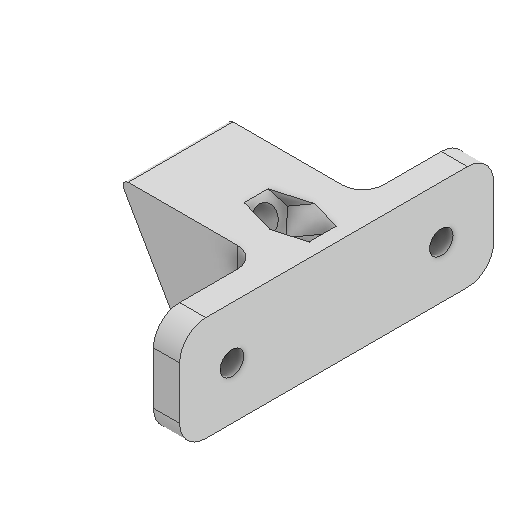
# Autodesk Inventor part: 3DP_PLA_Alu_Frame_Brace_REVB
Saved by Autodesk Inventor 2027 (Build 310192060, 192F)
## iProperties
Created: 2026-03-01
Part Number: 3DP_PLA_Alu_Frame_Brace_REVB
Material: Generic
Document SubType Name: Modeling
Designer: User
Density: 1 g/cm^3
Appearance: Default
Author: User
Autodesk Inventor part; units mm, degrees
ref_plane "YZ Plane" through (0, 0, 0) normal (1, 0, 0) x (0, 1, 0)
sketch "Sketch1" plane through (0, 0, 0) normal (0, 0, 1) x (1, 0, 0)
  line L0 (-5, 10) -> (0, 10)
  line L1 (0, 10) -> (0, -10)
  line L2 (0, -10) -> (-5, -10)
  line L3 (-5, -10) -> (-5, 10)
  point P0 (0, 0)
  point P1 (0, 0)
  dimension "d0" = 20
  dimension "d1" = 10
  dimension "d2" = 5
  constraints: 8 end point, 2 parallel, 1 horizontal, 1 midpoint, 1 perpendicular
  measures "d0" distance between parallel lines of L2 L0
  measures "d1" distance from line of point (0, 0) L0
  measures "d2" distance of L0.start L0.end
extrude "Extrusion1" add sketch "Sketch1" along normal blind 60
ref_plane "Work Plane1" through (0, 0, 20) normal (0, 0, -1) x (-1, 0, 0)
sketch "Sketch2" plane through (0, 0, 20) normal (0, 0, -1) x (-1, 0, 0)
  line L0 (5, -10) -> (0, -10) projected
  line L1 (0, -10) -> (0, 10) projected
  line L2 (0, 10) -> (5, 10) projected
  line L3 (5, 10) -> (5, -10) projected
  line L4 (5, 10) -> (20, 10)
  line L5 (20, 10) -> (20, -10)
  line L6 (20, -10) -> (5, -10)
  line L7 (20, -10) -> (31.547, 10)
  line L8 (20, -10) -> (39.401, -10) construction
  line L9 (20, 10) -> (31.547, 10)
  point P0 (0, 0)
  dimension "d6" = 15
  dimension "d8" = 60
  constraints: 12 end point, 3 horizontal, 2 perpendicular
  measures "d6" distance of L5.end L0.start
  measures "d8" angle of L8 L7
extrude "Extrusion2" add sketch "Sketch2" against normal blind 20 contours L3 L4 L5 L6 | L5 L9 L7
sketch "Sketch4" plane through (-20, -10, 40) normal (-0.866, -0.5, 0) x (-0.5, 0.866, 0)
  line L0 (0, 20) -> (23.094, 20) projected
  line L1 (0, 20) -> (0, 0) projected
  line L2 (23.094, 0) -> (0, 0) projected
  line L3 (23.094, 20) -> (23.094, 0) projected
  point P0 (-1.3397, 40)
  point P1 (11.547, 10)
  point P2 (0, 10)
  dimension "d11" = 23.094
  dimension "d12" = 20
  dimension "d13" = 10
  dimension "d14" = 11.547
  constraints: 1 midpoint
  measures "d11" distance from line of point (0, 10) L3
  measures "d12" distance of L0.start L1.end
  measures "d13" distance from line of L0 point (11.547, 10)
  measures "d14" distance from line of L1 point (11.547, 10)
hole "Hole1" at (-25.7735, 0, 30) direction (0.866, 0.5, 0) diameter 4.5 end through all
ref_plane "Work Plane2" through (1.6506, 2.5, 40) normal (-0.866, -0.5, 0) x (-0.5, 0.866, 0)
sketch "Sketch5" plane through (1.6506, 2.5, 40) normal (-0.866, -0.5, 0) x (-0.5, 0.866, 0)
  circle A0 centre (11.547, 10) radius 2.25 projected
  line L0 (15.247, 7.8638) -> (11.547, 5.7276)
  line L1 (11.547, 5.7276) -> (7.847, 7.8638)
  line L2 (7.847, 7.8638) -> (7.847, 12.1362)
  line L3 (7.847, 12.1362) -> (11.547, 14.2724)
  line L4 (11.547, 14.2724) -> (15.247, 12.1362)
  line L5 (15.247, 12.1362) -> (15.247, 7.8638)
  point P0 (-1.3397, 40)
  point P1 (11.547, 10)
  point P2 (9.8205, 8.5572)
  point P3 (9.8205, 11.4428)
  dimension "d23" = 7.4
  constraints: 12 end point, 1 coincident, 13 other
  measures "d23" distance between parallel lines of L2 L5
extrude "Extrusion3" cut sketch "Sketch5" along normal blind 11 contours A0 | L0 L1 L2 L3 L4 L5
sketch "Sketch6" plane through (-5, -10, 60) normal (-1, 0, 0) x (0, 0, 1)
  line L0 (-40, 0) -> (-40, 20) projected
  line L1 (-60, 20) -> (-40, 20) projected
  line L2 (-60, 20) -> (-60, 0) projected
  line L3 (-60, 0) -> (-40, 0) projected
  line L4 (-20, 20) -> (-20, 0) projected
  line L5 (-20, 0) -> (0, 0) projected
  line L6 (0, 20) -> (0, 0) projected
  line L7 (-20, 20) -> (0, 20) projected
  point P0 (-60, 10)
  point P1 (-50, 10)
  point P2 (-10, 10)
  dimension "d2" = 5
  dimension "d26" = 20
  dimension "d27" = 20
  dimension "d28" = 10
  dimension "d29" = 10
  dimension "d30" = 10
  dimension "d31" = 10
  measures "d26" distance between parallel lines of L0 L2
  measures "d27" distance of L1.start L2.end
  measures "d28" distance from line of L2 point (-50, 10)
  measures "d29" distance from line of L3 point (-50, 10)
  measures "d30" distance from line of L5 point (-10, 10)
  measures "d31" distance from line of L6 point (-10, 10)
hole "Hole2" at (-5, 0, 10) at (-5, 0, 50) direction (1, 0, 0) diameter 4.5 end through all
fillet "Fillet1" radius 5 4 edges at (-2.5, 10, 60) (-2.5, -10, 60) (-2.5, -10, 0) (-2.5, 10, 0)
fillet "Fillet2" radius 1 2 edges at (-31.547, 10, 30) (-20, -10, 30)
fillet "Fillet3" radius 4 2 edges at (-5, 0, 40) (-5, 0, 20)
equation "\"d13\" = 0.5 * d12"
equation "\"d14\" = 0.5 * d11"
body "Solid1"
